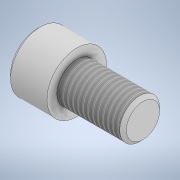
# Autodesk Inventor part: 24-10-25-screwLawrence-A2213271-v1
Saved by Autodesk Inventor 2022 (Build 260153000, 153)
## iProperties
Created: 2024-10-25
Part Number: 24-10-25-screwLawrence-A2213271-v1
Material: Generic
Document SubType Name: Modeling
Designer: Dell
Density: 1 g/cm^3
Appearance: Default
Author: Dell
Autodesk Inventor part; units mm, degrees
ref_plane "YZ Plane" through (0, 0, 0) normal (1, 0, 0) x (0, 1, 0)
ref_plane "XZ Plane" through (0, 0, 0) normal (0, 1, 0) x (-1, 0, 0)
ref_plane "XY Plane" through (0, 0, 0) normal (0, 0, 1) x (1, 0, 0)
sketch "Sketch1" plane through (0, 0, 0) normal (0, 0, 1) x (1, 0, 0)
  line L0 (0, 0) -> (0, 6)
  line L1 (0, 6) -> (-20, 6)
  line L2 (-20, 6) -> (-20, 9)
  line L3 (-20, 9) -> (-32, 9)
  line L4 (-32, 9) -> (-32, 0)
  line L5 (-32, 0) -> (0, 0)
  dimension "d0" = 6
  dimension "d1" = 20
  dimension "d2" = 12
  dimension "d3" = 9
  constraints: 12 end point, 5 perpendicular, 1 vertical
  measures "d0" distance of L0.start L0.end
  measures "d1" distance of L0.end L1.end
  measures "d2" distance of L2.end L3.end
  measures "d3" distance of L3.end L4.end
revolve "Revolution1" add sketch "Sketch1" angle 360 about axis through (-32, 0, 0) along (1, 0, 0)
chamfer "Chamfer1" distance 1 angle 45 2 edges at (-32, -9, 0) (0, -6, 0)
sketch "Sketch2" plane through (-32, 0, 0) normal (-1, 0, 0) x (0, 0, 1)
  line L0 (5, 2.8868) -> (5, -2.8868)
  line L1 (5, -2.8868) -> (0, -5.7735)
  line L2 (0, -5.7735) -> (-5, -2.8868)
  line L3 (-5, -2.8868) -> (-5, 2.8868)
  line L4 (-5, 2.8868) -> (0, 5.7735)
  line L5 (0, 5.7735) -> (5, 2.8868)
  point P0 (0, 0)
  point P1 (0, 0)
  dimension "d8" = 10
  constraints: 12 end point, 1 coincident, 1 vertical alignment, 13 other
  measures "d8" distance between parallel lines of L1 L4
extrude "Extrusion1" cut sketch "Sketch2" against normal blind 10
thread "Thread1" size "M12x1.5" class "6g" standard "ISO Metric profile" full length
body "Solid1"
